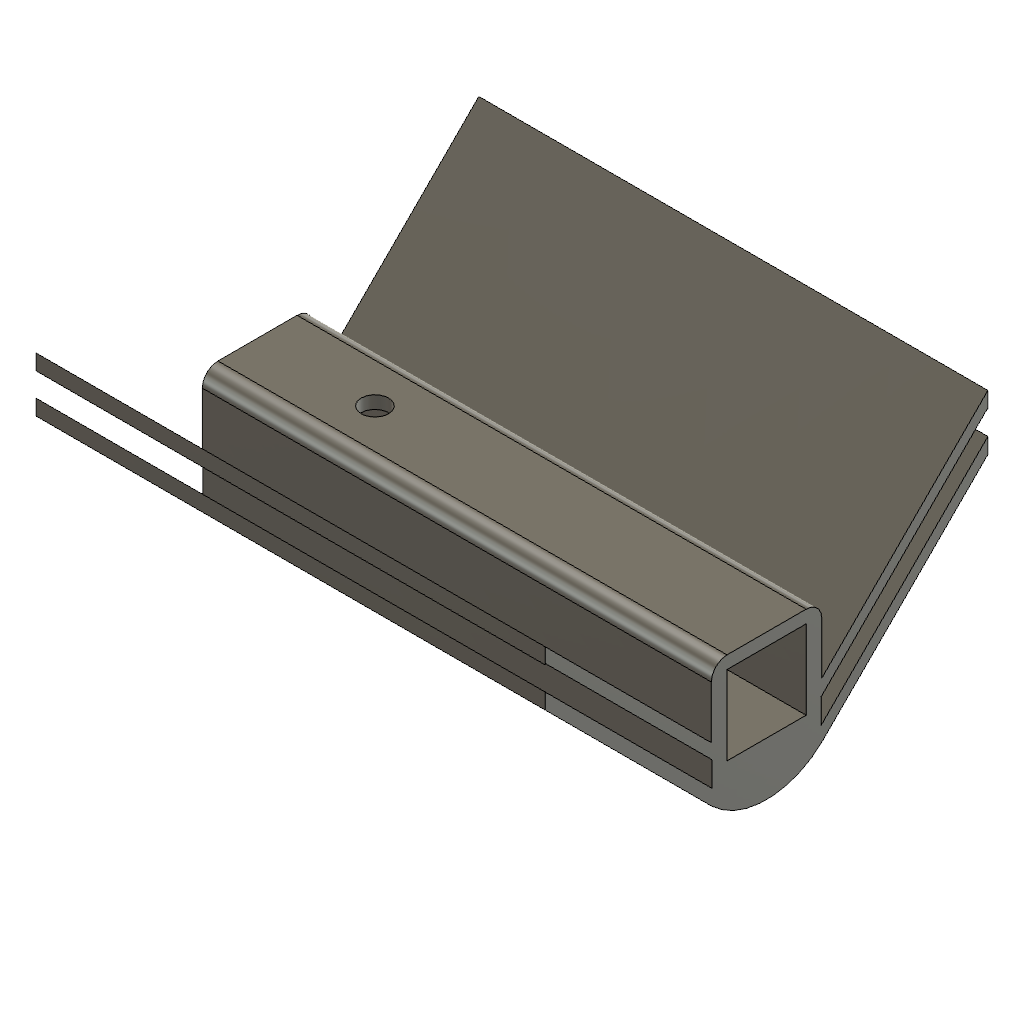
rc-airplanes-trainer-airplane-fusion-parts-empannage-clip-v-tail-45 (Autodesk Fusion 360 design; units mm, degrees)
Autodesk Fusion 360 part; units mm, degrees
sketch "Sketch1" plane through (0, 0, 0) normal (1, 0, 0) x (0, 0, -1)
  line L0 (-12.95, 7.55) -> (-12.95, -2.55)
  line L1 (-23.05, 7.55) -> (-12.95, 7.55)
  line L2 (-10.9506, -1.5393) -> (10.2626, 19.674)
  line L3 (-12.95, 7.55) -> (-12.95, -2.55)
  line L4 (-10.9506, 0.5536) -> (10.2626, 21.7668)
  line L5 (-23.05, 7.55) -> (-12.95, 7.55)
  line L6 (-12.95, -2.55) -> (-23.05, -2.55)
  line L7 (-25.0494, -1.5393) -> (-46.2626, 19.674)
  line L8 (-10.9506, 9.175) -> (-25.0494, 9.175)
  line L9 (-25.0494, -4.5393) -> (-46.2626, 16.674)
  line L10 (-25.0494, 0.4607) -> (-46.2626, 21.674)
  line L11 (-46.2626, 19.674) -> (-46.2626, 21.674)
  line L12 (-12.95, -2.55) -> (-23.05, -2.55)
  line L13 (-25.0494, 9.175) -> (-10.9506, 9.175)
  line L14 (-23.05, -2.55) -> (-23.05, 7.55)
  line L15 (-23.05, -2.55) -> (-23.05, 7.55)
  line L16 (10.2626, 19.674) -> (10.2626, 21.7668)
  line L17 (-10.9506, -4.5393) -> (10.2626, 16.674)
  line L18 (-25.0494, -6.5393) -> (-46.2626, 14.674)
  line L19 (-25.0494, -6.5393) -> (4.9506, -6.5393) construction
  line L20 (-10.9506, -6.5393) -> (10.2626, 14.674)
  line L21 (-25.0494, -6.5393) -> (-25.0494, 9.175)
  line L22 (-10.9506, 9.175) -> (-10.9506, -6.5393)
  arc A0 (-25.0494, -6.5393) -> (-10.9506, -6.5393) centre (-18, 0.8018) ccw
  line L23 (10.2626, 16.674) -> (10.2626, 14.674)
  line L24 (-46.2626, 16.674) -> (-46.2626, 14.674)
  dimension "d1" = 3
  dimension "d2" = 30
  dimension "d4" = 2
  dimension "d5" = 2
  dimension "d8" = 30
  dimension "d11" = 30
  dimension "d13" = 30
  dimension "d16" = 2
  dimension "d17" = 2
  dimension "d18" = 135
  dimension "d19" = 30
  dimension "d21" = 30
  constraint coincident L8.end L13.start
  constraint horizontal L13
  constraint horizontal L5
  constraint vertical L3
  constraint horizontal L12
  constraint vertical L15
  constraint coincident L0.end L3.end
  constraint coincident L1.start L5.start
  constraint horizontal L19
  constraint perpendicular L8 L21
  constraint perpendicular L19 L22
  constraint vertical L23
  constraint vertical L24
  measures "d1" distance of L9.start L7.start
  measures "d2" distance of L7.start L7.end
  measures "d4" distance of L7.end L10.end
  measures "d5" distance of L7.start L10.start
  measures "d8" distance of L17.end L17.start
  measures "d11" distance of L2.start L2.end
  measures "d13" distance of L4.end L4.start
  measures "d16" distance of L9.start L18.start
  measures "d17" distance of L17.start L20.start
  measures "d18" angle of L18 L19
  measures "d19" distance of L18.start L18.end
  measures "d21" distance of L20.start L20.end
extrude "Extrude1" add sketch "Sketch1" along normal blind 65
sketch "Sketch2" plane through (0, 9.175, 0) normal (0, 1, 0) x (-1, 0, 0)
  line L0 (0, 10.9506) -> (0, 25.0494)
  line L1 (0, 25.0494) -> (-65, 25.0494)
  line L2 (-65, 25.0494) -> (-65, 10.9506)
  line L3 (-65, 10.9506) -> (0, 10.9506)
  circle A0 centre (-15, 18) radius 1.75
extrude "Extrude2" cut sketch "Sketch2" against normal blind 35 contours A0
fillet "Fillet1" radius 2 2 edges at (32.5, 9.175, 25.0494) (32.5, 9.175, 10.9506)
extrude "Extrude3" cut 1 faces at (21.6667, 5.5318, 32.1205) along direction (0, 0.707107, -0.707107) blind 0.115
extrude "Extrude4" cut 1 faces at (43.3333, 5.5318, 3.8795) along direction (0, 0.707107, 0.707107) blind 0.115
sketch "Sketch3" plane through (65, 0, 0) normal (1, 0, 0) x (0, 0, -1)
  line L0 (10.1813, 19.7553) -> (10.2626, 19.674)
  line L1 (10.2626, 19.674) -> (10.2626, 21.7668)
  line L2 (10.2626, 21.7668) -> (-10.9506, 0.5536)
  line L3 (-10.9506, 0.5536) -> (-10.9506, 7.175)
  arc A0 (-10.9506, 7.175) -> (-12.9506, 9.175) centre (-12.9506, 7.175) ccw
  line L4 (-12.9506, 9.175) -> (-23.0494, 9.175)
  arc A1 (-23.0494, 9.175) -> (-25.0494, 7.175) centre (-23.0494, 7.175) ccw
  line L5 (-25.0494, 7.175) -> (-25.0494, 0.4607)
  line L6 (-25.0494, 0.4607) -> (-46.2626, 21.674)
  line L7 (-46.2626, 21.674) -> (-46.2626, 19.674)
  line L8 (-46.2626, 19.674) -> (-46.1813, 19.7553)
  line L9 (-46.1813, 19.7553) -> (-24.9681, -1.4579)
  line L10 (-24.9681, -1.4579) -> (-25.0494, -1.5393)
  line L11 (-25.0494, -1.5393) -> (-25.0494, -4.5393)
  line L12 (-25.0494, -4.5393) -> (-46.2626, 16.674)
  line L13 (-46.2626, 16.674) -> (-46.2626, 14.674)
  line L14 (-46.2626, 14.674) -> (-25.0494, -6.5393)
  arc A2 (-25.0494, -6.5393) -> (-10.9506, -6.5393) centre (-18, 0.8018) ccw
  line L15 (-10.9506, -6.5393) -> (10.2626, 14.674)
  line L16 (10.2626, 14.674) -> (10.2626, 16.674)
  line L17 (10.2626, 16.674) -> (-10.9506, -4.5393)
  line L18 (-10.9506, -4.5393) -> (-10.9506, -1.5393)
  line L19 (-10.9506, -1.5393) -> (-11.0319, -1.4579)
  line L20 (-11.0319, -1.4579) -> (10.1813, 19.7553)
  line L21 (-12.95, -2.55) -> (-23.05, -2.55)
  line L22 (-23.05, -2.55) -> (-23.05, 7.55)
  line L23 (-23.05, 7.55) -> (-12.95, 7.55)
  line L24 (-12.95, 7.55) -> (-12.95, -2.55)
  line L25 (-11.0319, -1.4579) -> (-11.0319, -4.6206)
  line L26 (-10.9506, -4.5393) -> (-11.0319, -4.6206)
  line L27 (-24.9681, -1.4579) -> (-24.9681, -4.6206)
  line L28 (-25.0494, -4.5393) -> (-24.9681, -4.6206)
  constraint coincident L19.end L20.start
  constraint parallel L18 L25
  constraint coincident L17.end L18.start
  constraint parallel L17 L26
  constraint coincident L9.end L10.start
  constraint parallel L11 L27
  constraint coincident L11.end L12.start
  constraint parallel L12 L28
extrude "Extrude5" cut sketch "Sketch3" against normal blind 65 contours L18 L19 L25 L26 | L10 L11 L27 L28
